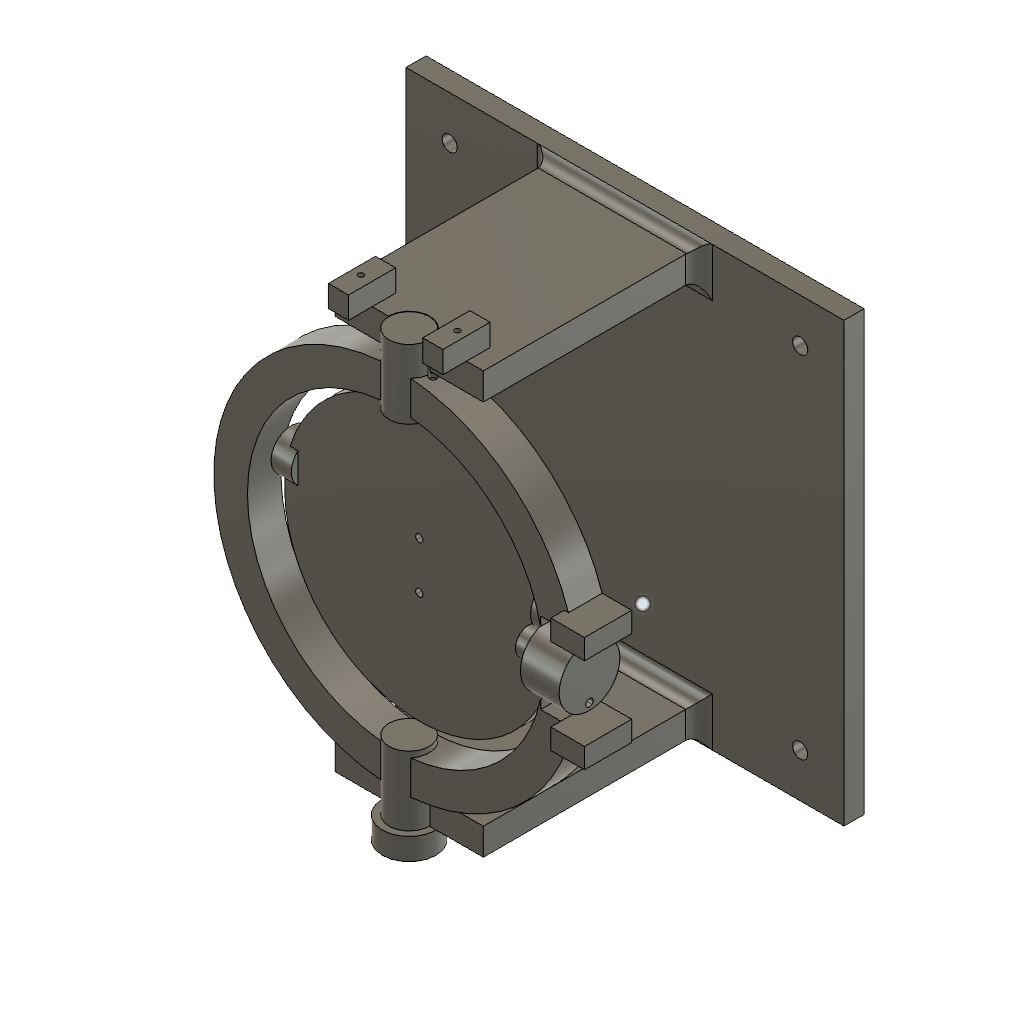
Gimbal2Axis_v2 (Autodesk Fusion 360 design; units mm, degrees)
part number: 2026-11-09-18-52-25-274
part number: 2026-11-09-18-52-25-463
part number: 2026-11-09-18-52-25-603
part number: 2026-11-09-18-52-25-742
part number: 2026-11-09-18-52-26-360
Autodesk Fusion 360 part; units mm, degrees
ref_plane "工作平面1" through (0, 0, 0) normal (0, 0, 1) x (1, 0, 0) in component "Disc"
sketch "草图1" plane through (0, 0, 0) normal (0, 0, 1) x (1, 0, 0) in component "Disc"
  circle A0 centre (0, 0) radius 40
extrude "拉伸1" add sketch "草图1" along normal blind 4 makes body 1 in component "Disc"
ref_plane "工作平面2" through (36, 0, 0) normal (1, 0, 0) x (0, 1, 0) in component "Disc"
sketch "草图2" plane through (36, 0, 0) normal (1, 0, 0) x (0, 0, -1) in component "Disc"
  circle A0 centre (0, 7) radius 7
extrude "拉伸2" add sketch "草图2" along normal blind 6 bodies 1 in component "Disc"
ref_plane "工作平面3" through (-42, 0, 0) normal (1, 0, 0) x (0, 1, 0) in component "Disc"
sketch "草图3" plane through (-42, 0, 0) normal (1, 0, 0) x (0, 0, -1) in component "Disc"
  circle A0 centre (0, 7) radius 6
extrude "拉伸3" add sketch "草图3" along normal blind 6 bodies 1 in component "Disc"
ref_plane "工作平面4" through (35, 0, 0) normal (1, 0, 0) x (0, 1, 0) in component "Disc"
sketch "草图4" plane through (35, 0, 0) normal (1, 0, 0) x (0, 0, -1) in component "Disc"
  circle A0 centre (0, 7) radius 4.1
extrude "拉伸4" cut sketch "草图4" along normal blind 7.5 bodies 1 in component "Disc"
ref_plane "工作平面5" through (-42.5, 0, 0) normal (1, 0, 0) x (0, 1, 0) in component "Disc"
sketch "草图5" plane through (-42.5, 0, 0) normal (1, 0, 0) x (0, 0, -1) in component "Disc"
  circle A0 centre (0, 7) radius 2.3
extrude "拉伸5" cut sketch "草图5" along normal blind 6.5 bodies 1 in component "Disc"
ref_plane "工作平面6" through (0, 0, -0.1) normal (0, 0, 1) x (1, 0, 0) in component "Disc"
sketch "草图6" plane through (0, 0, -0.1) normal (0, 0, 1) x (1, 0, 0) in component "Disc"
  line L0 (-11, -8.5) -> (11, -8.5)
  line L1 (11, -8.5) -> (11, 8.5)
  line L2 (11, 8.5) -> (-11, 8.5)
  line L3 (-11, 8.5) -> (-11, -8.5)
extrude "拉伸6" cut sketch "草图6" along normal blind 1.7 bodies 1 in component "Disc"
ref_plane "工作平面1" through (0, 0, 0) normal (0, 0, 1) x (1, 0, 0) in component "Hub"
sketch "草图1 (2)" plane through (0, 0, 0) normal (0, 0, 1) x (1, 0, 0) in component "Hub"
  circle A0 centre (0, 0) radius 9
extrude "拉伸1'" add sketch "草图1 (2)" along normal blind 11.5 separate body makes body 2 in component "Hub"
ref_plane "工作平面2" through (0, 0, 11.5) normal (0, 0, 1) x (1, 0, 0) in component "Hub"
sketch "草图2 (2)" plane through (0, 0, 11.5) normal (0, 0, 1) x (1, 0, 0) in component "Hub"
  circle A0 centre (0, 0) radius 4
extrude "拉伸2'" add sketch "草图2 (2)" along normal blind 6.5 bodies 2 in component "Hub"
ref_plane "工作平面3" through (0, 0, -0.5) normal (0, 0, 1) x (1, 0, 0) in component "Hub"
sketch "草图3 (2)" plane through (0, 0, -0.5) normal (0, 0, 1) x (1, 0, 0) in component "Hub"
  circle A0 centre (0, 7) radius 1.1
extrude "拉伸7" cut sketch "草图3 (2)" along normal blind 12.5 bodies 1 in component "Disc"
extrude "拉伸3'" cut sketch "草图3 (2)" along normal blind 12.5 bodies 2 in component "Hub"
ref_plane "工作平面4" through (0, 0, -0.5) normal (0, 0, 1) x (1, 0, 0) in component "Hub"
sketch "草图4 (2)" plane through (0, 0, -0.5) normal (0, 0, 1) x (1, 0, 0) in component "Hub"
  circle A0 centre (0, -7) radius 1.1
extrude "拉伸8" cut sketch "草图4 (2)" along normal blind 12.5 bodies 1 in component "Disc"
extrude "拉伸4'" cut sketch "草图4 (2)" along normal blind 12.5 bodies 2 in component "Hub"
ref_plane "工作平面1" through (0, 0, 0) normal (0, 0, 1) x (1, 0, 0) in component "Ring"
sketch "草图1 (3)" plane through (0, 0, 0) normal (0, 0, 1) x (1, 0, 0) in component "Ring"
  circle A0 centre (0, 0) radius 54
  circle A1 centre (0, 0) radius 44
extrude "拉伸1''" add sketch "草图1 (3)" along normal blind 10 separate body makes body 3 in component "Ring"
ref_plane "工作平面2" through (0, 0, 0) normal (0, 0, 1) x (1, 0, 0) in component "Ring"
sketch "草图2 (3)" plane through (0, 0, 0) normal (0, 0, 1) x (1, 0, 0) in component "Ring"
  line L0 (43, -12) -> (55, -12)
  line L1 (55, -12) -> (55, 12)
  line L2 (55, 12) -> (43, 12)
  line L3 (43, 12) -> (43, -12)
extrude "拉伸2''" cut sketch "草图2 (3)" along normal blind 10 bodies 3 in component "Ring"
ref_plane "工作平面3" through (0, 0, 0) normal (0, 0, 1) x (1, 0, 0) in component "Ring"
sketch "草图3 (3)" plane through (0, 0, 0) normal (0, 0, 1) x (1, 0, 0) in component "Ring"
  line L0 (50, 11) -> (60, 11)
  line L1 (60, 11) -> (60, 17)
  line L2 (60, 17) -> (50, 17)
  line L3 (50, 17) -> (50, 11)
extrude "拉伸3''" add sketch "草图3 (3)" along normal blind 14 bodies 3 in component "Ring"
ref_plane "工作平面4" through (0, 0, 0) normal (0, 0, 1) x (1, 0, 0) in component "Ring"
sketch "草图4 (3)" plane through (0, 0, 0) normal (0, 0, 1) x (1, 0, 0) in component "Ring"
  line L0 (50, -17) -> (60, -17)
  line L1 (60, -17) -> (60, -11)
  line L2 (60, -11) -> (50, -11)
  line L3 (50, -11) -> (50, -17)
extrude "拉伸4''" add sketch "草图4 (3)" along normal blind 14 bodies 3 in component "Ring"
ref_plane "工作平面5" through (49, 0, 0) normal (1, 0, 0) x (0, 1, 0) in component "Ring"
sketch "草图5 (2)" plane through (49, 0, 0) normal (1, 0, 0) x (0, 0, -1) in component "Ring"
  circle A0 centre (14.3, 6) radius 0.8
ref_plane "工作平面6" through (0, 42, 0) normal (0, 1, 0) x (0, 0, 1) in component "Ring"
sketch "草图6 (2)" plane through (0, 42, 0) normal (0, 1, 0) x (1, 0, 0) in component "Ring"
  circle A0 centre (0, -6) radius 6
extrude "拉伸5'" add sketch "草图6 (2)" along normal blind 20.5 bodies 3 in component "Ring"
ref_plane "工作平面7" through (0, -62.5, 0) normal (0, 1, 0) x (0, 0, 1) in component "Ring"
sketch "草图7" plane through (0, -62.5, 0) normal (0, 1, 0) x (1, 0, 0) in component "Ring"
  circle A0 centre (0, -6) radius 6
extrude "拉伸6'" add sketch "草图7" along normal blind 20.5 bodies 3 in component "Ring"
ref_plane "工作平面8" through (0, 52.5, 0) normal (0, 1, 0) x (0, 0, 1) in component "Ring"
sketch "草图8" plane through (0, 52.5, 0) normal (0, 1, 0) x (1, 0, 0) in component "Ring"
  circle A0 centre (7, -6) radius 1.1
extrude "拉伸7'" cut sketch "草图8" along normal blind 12 bodies 3 in component "Ring"
ref_plane "工作平面9" through (0, 52.5, 0) normal (0, 1, 0) x (0, 0, 1) in component "Ring"
sketch "草图9" plane through (0, 52.5, 0) normal (0, 1, 0) x (1, 0, 0) in component "Ring"
  circle A0 centre (-7, -6) radius 1.1
extrude "拉伸8'" cut sketch "草图9" along normal blind 12 bodies 3 in component "Ring"
ref_plane "工作平面10" through (-55, 0, 0) normal (1, 0, 0) x (0, 1, 0) in component "Ring"
sketch "草图10" plane through (-55, 0, 0) normal (1, 0, 0) x (0, 0, -1) in component "Ring"
  circle A0 centre (0, 6) radius 1.7
extrude "拉伸9" cut sketch "草图10" along normal blind 12 bodies 3 in component "Ring"
ref_plane "工作平面11" through (0, -63, 0) normal (0, 1, 0) x (0, 0, 1) in component "Ring"
sketch "草图11" plane through (0, -63, 0) normal (0, 1, 0) x (1, 0, 0) in component "Ring"
  circle A0 centre (0, -6) radius 2.3
extrude "拉伸10" cut sketch "草图11" along normal blind 6.5 bodies 3 in component "Ring"
ref_plane "工作平面1" through (0, 0, 0) normal (0, 0, 1) x (1, 0, 0) in component "Frame"
sketch "草图1 (4)" plane through (0, 0, 0) normal (0, 0, 1) x (1, 0, 0) in component "Frame"
  line L0 (-65, -65) -> (65, -65)
  line L1 (65, -65) -> (65, 65)
  line L2 (65, 65) -> (-65, 65)
  line L3 (-65, 65) -> (-65, -65)
extrude "拉伸1'''" add sketch "草图1 (4)" along normal blind 6 separate body makes body 4 in component "Frame"
ref_plane "工作平面2" through (0, 0, 6) normal (0, 0, 1) x (1, 0, 0) in component "Frame"
sketch "草图2 (4)" plane through (0, 0, 6) normal (0, 0, 1) x (1, 0, 0) in component "Frame"
  line L0 (-22, 54.5) -> (22, 54.5)
  line L1 (22, 54.5) -> (22, 62.5)
  line L2 (22, 62.5) -> (-22, 62.5)
  line L3 (-22, 62.5) -> (-22, 54.5)
extrude "拉伸2'''" add sketch "草图2 (4)" along normal blind 64 bodies 4 in component "Frame"
ref_plane "工作平面3" through (0, 0, 6) normal (0, 0, 1) x (1, 0, 0) in component "Frame"
sketch "草图3 (4)" plane through (0, 0, 6) normal (0, 0, 1) x (1, 0, 0) in component "Frame"
  line L0 (-22, -62.5) -> (22, -62.5)
  line L1 (22, -62.5) -> (22, -54.5)
  line L2 (22, -54.5) -> (-22, -54.5)
  line L3 (-22, -54.5) -> (-22, -62.5)
extrude "拉伸3'''" add sketch "草图3 (4)" along normal blind 64 bodies 4 in component "Frame"
ref_plane "工作平面4" through (0, -63.5, 0) normal (0, 1, 0) x (0, 0, 1) in component "Frame"
sketch "草图4 (4)" plane through (0, -63.5, 0) normal (0, 1, 0) x (1, 0, 0) in component "Frame"
  circle A0 centre (0, -70) radius 6.15
extrude "拉伸4'''" cut sketch "草图4 (4)" along normal blind 11 bodies 4 in component "Frame"
ref_plane "工作平面5" through (0, 53.5, 0) normal (0, 1, 0) x (0, 0, 1) in component "Frame"
sketch "草图5 (3)" plane through (0, 53.5, 0) normal (0, 1, 0) x (1, 0, 0) in component "Frame"
  circle A0 centre (0, -70) radius 6.15
extrude "拉伸5''" cut sketch "草图5 (3)" along normal blind 11 bodies 4 in component "Frame"
ref_plane "工作平面6" through (0, 0, 63) normal (0, 0, 1) x (1, 0, 0) in component "Frame"
sketch "草图6 (3)" plane through (0, 0, 63) normal (0, 0, 1) x (1, 0, 0) in component "Frame"
  line L0 (11, 62.5) -> (17, 62.5)
  line L1 (17, 62.5) -> (17, 69)
  line L2 (17, 69) -> (11, 69)
  line L3 (11, 69) -> (11, 62.5)
extrude "拉伸6''" add sketch "草图6 (3)" along normal blind 14 bodies 4 in component "Frame"
ref_plane "工作平面7" through (0, 0, 63) normal (0, 0, 1) x (1, 0, 0) in component "Frame"
sketch "草图7 (2)" plane through (0, 0, 63) normal (0, 0, 1) x (1, 0, 0) in component "Frame"
  line L0 (-17, 62.5) -> (-11, 62.5)
  line L1 (-11, 62.5) -> (-11, 69)
  line L2 (-11, 69) -> (-17, 69)
  line L3 (-17, 69) -> (-17, 62.5)
extrude "拉伸7''" add sketch "草图7 (2)" along normal blind 14 bodies 4 in component "Frame"
ref_plane "工作平面8" through (0, 61.5, 0) normal (0, 1, 0) x (0, 0, 1) in component "Frame"
sketch "草图8 (2)" plane through (0, 61.5, 0) normal (0, 1, 0) x (1, 0, 0) in component "Frame"
  circle A0 centre (14.3, -70) radius 0.8
extrude "拉伸8''" cut sketch "草图8 (2)" along normal blind 11 bodies 4 in component "Frame"
ref_plane "工作平面9" through (0, 61.5, 0) normal (0, 1, 0) x (0, 0, 1) in component "Frame"
sketch "草图9 (2)" plane through (0, 61.5, 0) normal (0, 1, 0) x (1, 0, 0) in component "Frame"
  circle A0 centre (-14.3, -70) radius 0.8
extrude "拉伸9'" cut sketch "草图9 (2)" along normal blind 11 bodies 4 in component "Frame"
ref_plane "工作平面10" through (0, -69, 0) normal (0, 1, 0) x (0, 0, 1) in component "Frame"
sketch "草图10 (2)" plane through (0, -69, 0) normal (0, 1, 0) x (1, 0, 0) in component "Frame"
  circle A0 centre (0, -70) radius 8
extrude "拉伸10'" add sketch "草图10 (2)" along normal blind 6.5 bodies 4 in component "Frame"
ref_plane "工作平面11" through (0, -70, 0) normal (0, 1, 0) x (0, 0, 1) in component "Frame"
sketch "草图11 (2)" plane through (0, -70, 0) normal (0, 1, 0) x (1, 0, 0) in component "Frame"
  circle A0 centre (0, -70) radius 1.7
extrude "拉伸11" cut sketch "草图11 (2)" along normal blind 10 bodies 4 in component "Frame"
ref_plane "工作平面12" through (0, 0, -0.1) normal (0, 0, 1) x (1, 0, 0) in component "Frame"
sketch "草图12" plane through (0, 0, -0.1) normal (0, 0, 1) x (1, 0, 0) in component "Frame"
  circle A0 centre (-52, -52) radius 2.25
extrude "拉伸12" cut sketch "草图12" along normal blind 7 bodies 4 in component "Frame"
ref_plane "工作平面13" through (0, 0, -0.1) normal (0, 0, 1) x (1, 0, 0) in component "Frame"
sketch "草图13" plane through (0, 0, -0.1) normal (0, 0, 1) x (1, 0, 0) in component "Frame"
  circle A0 centre (52, -52) radius 2.25
extrude "拉伸13" cut sketch "草图13" along normal blind 7 bodies 4 in component "Frame"
ref_plane "工作平面14" through (0, 0, -0.1) normal (0, 0, 1) x (1, 0, 0) in component "Frame"
sketch "草图14" plane through (0, 0, -0.1) normal (0, 0, 1) x (1, 0, 0) in component "Frame"
  circle A0 centre (-52, 52) radius 2.25
extrude "拉伸14" cut sketch "草图14" along normal blind 7 bodies 4 in component "Frame"
ref_plane "工作平面15" through (0, 0, -0.1) normal (0, 0, 1) x (1, 0, 0) in component "Frame"
sketch "草图15" plane through (0, 0, -0.1) normal (0, 0, 1) x (1, 0, 0) in component "Frame"
  circle A0 centre (52, 52) radius 2.25
extrude "拉伸15" cut sketch "草图15" along normal blind 7 bodies 4 in component "Frame"
fillet "圆角1" radius 4 8 edges at (0, 62.5, 6) (0, -54.5, 6) (22, -58.5, 6) (0, -62.5, 6) (-22, -58.5, 6) (22, 58.5, 6) (0, 54.5, 6) (-22, 58.5, 6) on bodies 4 in component "Frame"
component "Disc" placed x (1, 0, 0) y (0, 1, 0) z (0, 0, 1) at (0, 0, 0)
component "Hub" placed x (1, 0, 0) y (0, 1, 0) z (0, 0, 1) at (0, 0, 0)
component "Ring" placed x (1, 0, 0) y (0, 1, 0) z (0, 0, 1) at (0, 0, 0)
component "Frame" placed x (1, 0, 0) y (0, 1, 0) z (0, 0, 1) at (0, 0, 0)
